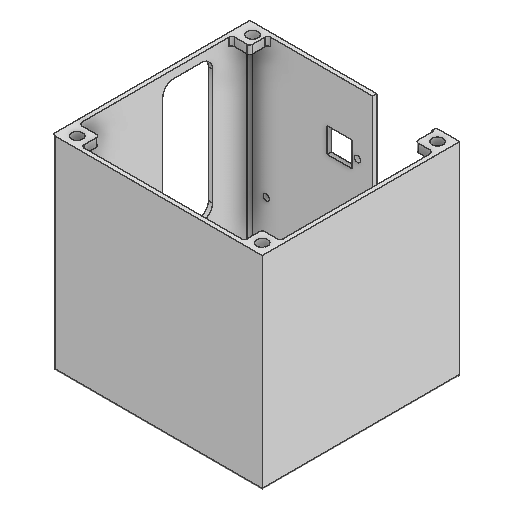
# Autodesk Inventor part: cosmic-ray-detector-v2-enclosure-fdm-body
Saved by Autodesk Inventor 2025.2 (Build 292293000, 293)
## iProperties
Created: 2026-02-25
Part Number: cosmic-ray-detector-v2-enclosure-fdm-body
Material: Generic
Document SubType Name: Modeling
Designer: kaduo
Density: 1 g/cm^3
Appearance: Default
Author: kaduo
Autodesk Inventor part; units mm, degrees
ref_plane "YZ Plane" through (0, 0, 0) normal (1, 0, 0) x (0, 1, 0)
ref_plane "XZ Plane" through (0, 0, 0) normal (0, 1, 0) x (-1, 0, 0)
ref_plane "XY Plane" through (0, 0, 0) normal (0, 0, 1) x (1, 0, 0)
sketch "Sketch1" plane through (0, 0, 0) normal (0, 0, 1) x (1, 0, 0)
  line L0 (0, 0) -> (-63, 0)
  line L1 (-63, 0) -> (-63, -66)
  line L2 (-63, -66) -> (0, -66)
  line L3 (0, -66) -> (0, 0)
  circle A0 centre (-60, -50) radius 1.1
  circle A1 centre (-3, -50) radius 1.1
  line L4 (0, 1) -> (-21.5, 1)
  line L5 (-21.5, 1) -> (-21.5, -47)
  line L6 (-21.5, -47) -> (0, -47)
  line L7 (0, -47) -> (0, 1)
  line L8 (-38, -25.5) -> (-29, -25.5)
  line L9 (-29, -25.5) -> (-29, -16.5)
  line L10 (-29, -16.5) -> (-38, -16.5)
  line L11 (-38, -16.5) -> (-38, -25.5)
  line L12 (7, 1) -> (-66, 1)
  line L13 (-66, 1) -> (-66, -73)
  line L14 (-66, -73) -> (7, -73)
  line L15 (7, -73) -> (7, 1)
  circle A2 centre (-27, -21.5) radius 1.1
  point P0 (-10.75, 1)
  point P1 (-21.5, 0)
  dimension "d0" = 63
  dimension "d1" = 66
  dimension "d10" = 2.2
  dimension "d11" = 2.2
  dimension "d15" = 0
  dimension "d16" = 48
  dimension "d17" = 21.5
  dimension "d18" = 9
  dimension "d19" = 9
  dimension "d20" = 16.5
  dimension "d21" = 25
  dimension "d22" = 3
  dimension "d23" = 7
  dimension "d24" = 7
  dimension "d25" = 1
  dimension "d50" = 2.2
  dimension "d51" = 27
  dimension "d52" = 21.5
  dimension "d53" = 50
  dimension "d54" = 50
  dimension "d55" = 0
  constraints: 32 end point, 8 parallel, 4 horizontal, 4 perpendicular, 3 centre point, 2 coincident, 1 midpoint
  measures "d0" distance of L2.end L1.end
  measures "d1" distance of L1.end L0.end
  measures "d10" diameter of A0
  measures "d11" diameter of A1
  measures "d15" distance between parallel lines of L3 L7
  measures "d16" distance from line of point (-10.75, 1) L6
  measures "d17" distance between parallel lines of L7 L5
  measures "d18" distance of L10.end L9.end
  measures "d19" distance of L9.end L8.end
  measures "d20" distance between parallel lines of L0 L10
  measures "d21" distance between parallel lines of L1 L11
  measures "d22" distance between parallel lines of L1 L13
  measures "d23" distance between parallel lines of L15 L3
  measures "d24" distance between parallel lines of L2 L14
  measures "d25" distance between parallel lines of L12 L0
  measures "d50" diameter of A2
  measures "d51" distance from line of L3 A2.centre
  measures "d52" distance from line of L0 A2.centre
  measures "d53" distance from line of L0 A0.centre
  measures "d54" distance from line of L0 point (-3, -50)
  measures "d55" distance between parallel lines of L12 L4
extrude "Extrusion1" add sketch "Sketch1" along normal blind 1.5 contours L7 L12 L15 L14 L13 L5 L0 L1 L2 L3 | L5 L6 L3 L2 L1 L0
sketch "Sketch2" plane through (-66, -73, 0) normal (0, -1, 0) x (1, 0, 0)
  line L0 (0, 0) -> (0, 1.5) projected
  line L1 (0, 0) -> (73, 0)
  line L2 (73, 0) -> (73, 70)
  line L3 (73, 70) -> (0, 70)
  line L4 (0, 70) -> (0, 0)
  line L5 (73, 0) -> (73, 1.5) projected
  point P0 (66, 0)
  point P1 (73, 0.75)
  dimension "d27" = 70
  dimension "d49" = 0
  constraints: 8 end point, 2 parallel, 1 horizontal, 1 midpoint, 1 perpendicular
  measures "d27" distance of L2.end L1.end
  measures "d49" distance from line of point (73, 0.75) L2
extrude "Extrusion2" add sketch "Sketch2" against normal blind 1.5
sketch "Sketch3" plane through (-66, -73, 0) normal (0, -1, 0) x (1, 0, 0)
  line L0 (17.5, 29) -> (46.5, 29)
  line L1 (46.5, 29) -> (46.5, 48)
  line L2 (46.5, 48) -> (17.5, 48)
  line L3 (17.5, 48) -> (17.5, 29)
  line L4 (0, 0) -> (0, 70) projected
  line L5 (0, 0) -> (73, 0) projected
  line L6 (73, 0) -> (73, 70) projected
  line L7 (73, 70) -> (0, 70) projected
  circle A0 centre (61, 25) radius 3.5
  line L8 (73, 25) -> (53, 25)
  circle A1 centre (53, 25) radius 4
  point P0 (66, 0)
  dimension "d30" = 29
  dimension "d31" = 19
  dimension "d32" = 17.5
  dimension "d33" = 29
  dimension "d36" = 12
  dimension "d37" = 45
  dimension "d38" = 7
  dimension "d39" = 20
  dimension "d40" = 8
  dimension "d73" = 0
  constraints: 10 end point, 3 coincident, 2 centre point, 2 parallel, 2 perpendicular, 1 horizontal, 1 point on line
  measures "d30" distance of L2.end L1.end
  measures "d31" distance of L1.end L0.end
  measures "d32" distance between parallel lines of L4 L3
  measures "d33" distance between parallel lines of L5 L0
  measures "d36" distance from line of L6 point (61, 25)
  measures "d37" distance from line of point (61, 25) L7
  measures "d38" diameter of A0
  measures "d39" distance of L8.start L8.end
  measures "d40" diameter of A1
  measures "d73" vertical distance of point (53, 25) point (61, 25)
extrude "Extrusion3" cut sketch "Sketch3" against normal up to surface (1.5 mm away) contours L3 L2 L1 L0 | L8 A0 | A0 L8 | A1
sketch "Sketch6" plane through (0, 0, 0) normal (0, 0, -1) x (-1, 0, 0)
  line L0 (-7, 1) -> (0, 1) projected
  line L1 (-3, 1) -> (-3, -73)
  line L2 (66, -73) -> (-7, -73) projected
  line L3 (21.5, 1) -> (66, 1) projected
  line L4 (62, 1) -> (62, -75)
  line L5 (66, 1) -> (66, -73) projected
  line L6 (66, -3) -> (-7, -3)
  line L7 (-7, -71.5) -> (-7, 1) projected
  line L8 (-7, -69) -> (66, -69)
  point P0 (0, 0)
  point P1 (-7, 0)
  point P2 (62, -3)
  point P3 (62, -69)
  point P4 (-3, -3)
  point P5 (-3, -69)
  point P6 (-3, -36)
  point P7 (62, -37)
  dimension "d59" = 4
  dimension "d60" = 4
  dimension "d61" = 4
  dimension "d62" = 4
  dimension "d70" = 76
  dimension "d71" = 66
  dimension "d74" = 0
  constraints: 14 point on line, 8 end point, 2 midpoint, 2 perpendicular, 1 horizontal, 1 vertical
  measures "d59" distance between parallel lines of L3 L6
  measures "d60" distance between parallel lines of L4 L5
  measures "d61" distance between parallel lines of L2 L8
  measures "d62" distance between parallel lines of L1 L7
  measures "d70" distance of L4.start L4.end
  measures "d71" distance between parallel lines of L8 L6
  measures "d74" distance from line of L7 L6.end
hole "Hole1" at (-62, -3, 0) at (-62, -69, 0) at (3, -3, 0) at (3, -69, 0) direction (0, 0, 1) diameter 2.2 depth 1.5
sketch "Sketch7" plane through (-66, -73, 0) normal (-1, 0, 0) x (0, 0, 1)
  line L0 (0, 74) -> (0, 0) projected
  line L1 (0, 0) -> (70, 0)
  line L2 (70, 0) -> (70, 74)
  line L3 (70, 74) -> (0, 74)
  line L4 (0, 74) -> (0, 0)
  dimension "d128" = 70
  dimension "d129" = 74
  constraints: 8 end point, 2 parallel, 1 horizontal, 1 perpendicular
  measures "d128" distance of L3.end L2.end
  measures "d129" distance of L2.end L1.end
extrude "Extrusion6" add sketch "Sketch7" along normal blind 1.5
sketch "Sketch8" plane through (7, -73, 0) normal (1, 0, 0) x (0, 0, -1)
  line L0 (0, 0) -> (-70, 0) projected
  line L1 (-70, 0) -> (-70, 74) projected
  line L2 (0, 0) -> (-70, 0)
  line L3 (-70, 0) -> (-70, 74)
  line L4 (-70, 74) -> (0, 74)
  line L5 (0, 74) -> (0, 0)
  constraints: 8 end point, 2 parallel, 1 horizontal, 1 perpendicular
extrude "Extrusion7" add sketch "Sketch8" along normal blind 1.5
sketch "Sketch9" plane through (-67.5, 1, 70) normal (0, 0, 1) x (1, 0, 0)
  line L0 (76, -74) -> (76, -0.0274) projected
  line L1 (1, 0) -> (76, 0)
  line L2 (76, 0) -> (76, -74)
  line L3 (76, -74) -> (1, -74)
  line L4 (1, -74) -> (1, 0)
  point P0 (67.5, -1)
  point P1 (76, -0.0274)
  constraints: 8 end point, 2 parallel, 1 horizontal, 1 perpendicular
extrude "Extrusion8" add sketch "Sketch9" along normal blind 1.5
sketch "Sketch10" plane through (-67.5, 1, 0) normal (0, 1, 0) x (1, 0, 0)
  line L0 (0, 0) -> (0, -71.5) projected
  line L1 (0, 0) -> (8, 0)
  line L2 (8, 0) -> (8, -8)
  line L3 (8, -8) -> (0, -8)
  line L4 (0, -8) -> (0, 0)
  line L5 (1, -71.5) -> (9, -71.5)
  line L6 (9, -71.5) -> (9, -63.5)
  line L7 (9, -63.5) -> (1, -63.5)
  line L8 (1, -63.5) -> (1, -71.5)
  line L9 (76, 0) -> (68, 0)
  line L10 (68, 0) -> (68, -8)
  line L11 (68, -8) -> (76, -8)
  line L12 (76, -8) -> (76, 0)
  line L13 (76, -71.5) -> (68, -71.5)
  line L14 (68, -71.5) -> (68, -63.5)
  line L15 (68, -63.5) -> (76, -63.5)
  line L16 (76, -63.5) -> (76, -71.5)
  point P0 (67.5, 0)
  point P1 (0, -43)
  point P2 (0.1119, -8)
  dimension "d30" = 29
  dimension "d31" = 19
  dimension "d32" = 17.5
  dimension "d33" = 29
  dimension "d81" = 8
  dimension "d82" = 8
  dimension "d83" = 8
  dimension "d84" = 8
  dimension "d85" = 8
  dimension "d86" = 8
  dimension "d87" = 8
  dimension "d88" = 8
  constraints: 32 end point, 8 parallel, 4 horizontal, 4 perpendicular, 2 point on line, 1 other
  measures "d81" distance of L2.end L3.end
  measures "d82" distance of L1.end L2.end
  measures "d83" distance of L7.end L6.end
  measures "d84" distance of L6.end L5.end
  measures "d85" distance of L11.end L10.end
  measures "d86" distance of L10.end L9.end
  measures "d87" distance of L14.end L15.end
  measures "d88" distance of L13.end L14.end
extrude "Extrusion9" add sketch "Sketch10" against normal blind 3
sketch "Sketch11" plane through (-67.5, 1, 0) normal (0, 1, 0) x (1, 0, 0)
  line L0 (1, -70) -> (1, -71.5) projected
  line L1 (46, 0) -> (0, 0) projected
  line L2 (76, -8) -> (76, 0) projected
  line L3 (76, 0) -> (67.5, 0) projected
  line L4 (76, -71.5) -> (1, -71.5) projected
  line L5 (76, -63.5) -> (76, -71.5) projected
  point P0 (5, -4)
  point P1 (72, -4)
  point P2 (5, -67.5)
  point P3 (72, -67.5)
  dimension "d91" = 4
  dimension "d92" = 4
  dimension "d93" = 4
  dimension "d94" = 4
  dimension "d95" = 4
  dimension "d96" = 4
  dimension "d97" = 4
  dimension "d98" = 4
  constraints: 1 other
  measures "d92" distance from line of point (5, -4) L1
  measures "d93" distance from line of L2 point (72, -4)
  measures "d94" distance from line of point (72, -4) L3
  measures "d95" distance from line of L4 point (5, -67.5)
  measures "d97" distance from line of L5 point (72, -67.5)
  measures "d98" distance from line of L4 point (72, -67.5)
hole "Hole2" at (4.5, 1, 4) at (4.5, 1, 67.5) at (-62.5, 1, 4) at (-62.5, 1, 67.5) direction (0, -1, 0) diameter 4 depth 3
sketch "Sketch13" plane through (-67.5, -73, 70) normal (0, 0, 1) x (1, 0, 0)
  line L0 (0, 74) -> (0, 0) projected
  line L1 (1.0286, 0.0017) -> (0, 0.0017)
  line L2 (0, 0.0017) -> (0, 74)
  line L3 (0, 74) -> (1.0286, 74)
  line L4 (1.0286, 74) -> (1.0286, 0.0017)
  point P0 (67.5, 73)
  point P1 (0, 0.0017)
  constraints: 8 end point, 2 parallel, 1 horizontal, 1 perpendicular
extrude "Extrusion10" add sketch "Sketch13" along normal blind 1.5
fillet "Fillet3" radius 1 26 edges at (-67.5, -35.9991, 71.5) (0.5, -0.5, 63.5) (7, -0.5, 63.5) (0.5, -0.5, 70) (0.5, -0.5, 8) (7, -0.5, 8) (-59.5, -0.5, 8) (-59.5, -0.5, 1.5) (-66, -0.5, 8) (-58.5, -0.5, 63.5) (-66, -0.5, 63.5) (-58.5, -0.5, 70) (7, -36.75, 1.5) (-66, -36.75, 1.5) (-29.5, -71.5, 70) (7, -71.5, 35.75) (-29.5, -71.5, 1.5) (-66, -71.5, 35.75) (-21.5, -47, 0.75) (0, -47, 0.75) (-48.5, -72.25, 48) (-48.5, -72.25, 29) (-19.5, -72.25, 29) (-19.5, -72.25, 48) (-29, -73, 71.5) (8.5, -73, 35.75)
sketch "Sketch14" plane through (-67.5, -73, 0) normal (-1, 0, 0) x (0, 0, 1)
  line L0 (29, 71) -> (19, 71)
  line L1 (15, 67) -> (15, 25)
  line L2 (19, 21) -> (29, 21)
  line L3 (33, 25) -> (33, 67)
  line L4 (0, 74) -> (70.5, 74) projected
  line L5 (0, 74) -> (0, 0) projected
  arc A0 (33, 67) -> (29, 71) centre (29, 67) ccw
  arc A1 (19, 71) -> (15, 67) centre (19, 67) ccw
  arc A2 (15, 25) -> (19, 21) centre (19, 25) ccw
  arc A3 (29, 21) -> (33, 25) centre (29, 25) ccw
  point P0 (0, 73)
  point P1 (15, 21)
  point P2 (15, 71)
  dimension "d130" = 3
  dimension "d131" = 50
  dimension "d132" = 15
  dimension "d133" = 18
  dimension "d134" = 4
  constraints: 8 end point, 8 point on circle, 8 tangent, 4 centre point, 4 point on line, 3 equal radius, 2 parallel, 1 horizontal, 1 perpendicular
  measures "d130" distance between parallel lines of L4 L0
  measures "d131" distance of point (15, 71) point (15, 21)
  measures "d132" distance between parallel lines of L5 L1
  measures "d133" distance between parallel lines of L1 L3
  measures "d134" radius of A0
extrude "Extrusion11" cut sketch "Sketch14" against normal up to surface (1.5 mm away)
body "Solid1"
